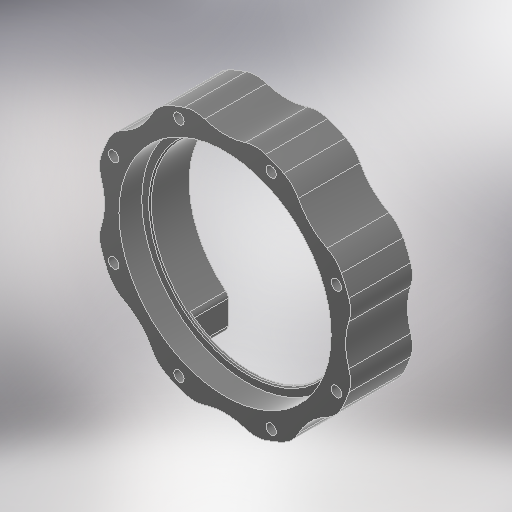
# Autodesk Inventor part: 3D_motor-spacer
Saved by Autodesk Inventor 2025.3 (Build 293356030, 356C)
## iProperties
Created: 2026-01-04
Part Number: 3D_motor-spacer
Material: 一般
Document SubType Name: Modeling
Designer: ibuki_ono
Density: 1 g/cm^3
Appearance: 滑らか - 黒
Author: ibuki_ono
## iProperties of the stored document 3D_motor-spacer_3D プリント.ipt
Created: 2026-02-11
Part Number: 3D_motor-spacer_3D プリント
Material: 一般
Document SubType Name: Modeling
Designer: ibuki_ono
Density: 1 g/cm^3
Appearance: 既定
Author: ibuki_ono
Autodesk Inventor part; units mm, degrees
ref_plane "YZ Plane" through (0, 0, 0) normal (1, 0, 0) x (0, 1, 0)
ref_plane "XZ Plane" through (0, 0, 0) normal (0, 1, 0) x (-1, 0, 0)
ref_plane "XY Plane" through (0, 0, 0) normal (0, 0, 1) x (1, 0, 0)
sketch "スケッチ1" plane through (0, 0, 0) normal (0, 0, 1) x (1, 0, 0)
  circle A0 centre (0, 0) radius 30
  circle A1 centre (0, 0) radius 40
  dimension "d0" = 60
  dimension "d1" = 80
  constraints: 2 centre point, 2 coincident
  measures "d0" diameter of A0
  measures "d1" diameter of A1
extrude "押し出し1" add sketch "スケッチ1" along normal mid plane 11
sketch "スケッチ2" plane through (0, 0, 5.5) normal (0, 0, 1) x (1, 0, 0)
  line L0 (0, 0) -> (34.1835, 14.1593) construction
  line L1 (0, 0) -> (30, 0) construction
  circle A0 centre (0, 0) radius 30 construction
  point P0 (34.1835, 14.1593)
  dimension "d21" = 37
  dimension "d23" = 22.5
  constraints: 4 end point, 1 coincident, 1 horizontal, 1 horizontal alignment, 1 other
  measures "d21" distance of L0.start L0.end
  measures "d23" angle of L0 L1
hole "穴1" at (34.1835, 14.1593, 5.5) direction (0, 0, -1) diameter 3.2 end through all
pattern_circular "円形状パターン1" count 8 over 360 about axis through (0, 0, 0) along (0, 0, 1) of "穴1"
sketch "スケッチ3" plane through (0, 0, 5.5) normal (0, 0, 1) x (1, 0, 0)
  circle A0 centre (34.1835, -14.1593) radius 1.6 projected
  circle A1 centre (14.1593, -34.1835) radius 1.6 projected
  circle A2 centre (-14.1593, -34.1835) radius 1.6 projected
  circle A3 centre (-34.1835, -14.1593) radius 1.6 projected
  circle A4 centre (-34.1835, 14.1593) radius 1.6 projected
  circle A5 centre (-14.1593, 34.1835) radius 1.6 projected
  circle A6 centre (14.1593, 34.1835) radius 1.6 projected
  circle A7 centre (34.1835, 14.1593) radius 1.6 projected
  circle A8 centre (0, 0) radius 40 projected
  circle A9 centre (0, 0) radius 30 projected
extrude "押し出し2" add sketch "スケッチ3" along normal blind 8 contours A8 | A9
sketch "スケッチ4" plane through (0, 0, 13.5) normal (0, 0, 1) x (1, 0, 0)
  circle A0 centre (0, 0) radius 32.55
  dimension "d18" = 65.1
  constraints: 1 centre point, 1 coincident
  measures "d18" diameter of A0
extrude "押し出し3" cut sketch "スケッチ4" against normal blind 7
sketch "スケッチ5" plane through (0, 0, 0) normal (0, 1, 0) x (-1, 0, 0)
  line L0 (30, -5.5) -> (-30, -5.5) projected
  line L1 (-30, 5.5) -> (30, 5.5) projected
  line L2 (-15.7593, 13.5) -> (-12.5593, 13.5) projected
  line L3 (-12.5593, -5.5) -> (-15.7593, -5.5) projected
  line L4 (12.5593, 13.5) -> (15.7593, 13.5) projected
  line L5 (15.7593, -5.5) -> (12.5593, -5.5) projected
  line L6 (-18, 5.5) -> (-18, -5.5)
  line L7 (18, 5.5) -> (18, -5.5)
  point P0 (0, 0)
  dimension "d42" = 36
  dimension "d43" = 18
  constraints: 4 end point, 4 point on line, 2 perpendicular
  measures "d42" distance between parallel lines of L7 L6
  measures "d43" distance from line of L7 point (0, 0)
extrude "押し出し4" cut sketch "スケッチ5" against normal through all
sketch "スケッチ6" plane through (0, 0, 5.5) normal (0, 0, -1) x (-1, 0, 0)
  arc A0 (18, -24) -> (-18, -24) centre (0, 0) ccw projected
  circle A1 centre (0, 0) radius 30
  point P0 (18, -24)
  constraints: 1 coincident, 3 other
extrude "押し出し5" cut sketch "スケッチ6" against normal through all
chamfer "面取り1" distance 0.4 angle 45 2 edges at (0, -30, 6.5) (0, 30, 6.5)
fillet "フィレット1" radius 2 8 edges at (-18, -35.7211, 2.75) (-18, -35.7211, -2.75) (-18, -24, 2.75) (-18, -24, -2.75) (18, -35.7211, -2.75) (18, -35.7211, 2.75) (18, -24, 2.75) (18, -24, -2.75)
sketch "スケッチ7" plane through (0, 0, 13.5) normal (0, 0, 1) x (1, 0, 0)
  circle A0 centre (0, 0) radius 40 projected
  arc A1 (-8.7719, 39.0263) -> (8.7719, 39.0263) centre (0, 57) ccw
  dimension "d34" = 20
  dimension "d35" = 57
  constraints: 4 point on circle, 1 centre point, 1 horizontal alignment, 1 vertical alignment
  measures "d34" radius of A1
  measures "d35" distance of point (0, 0) A1.centre
extrude "押し出し6" cut sketch "スケッチ7" against normal through all contours A1 A0 picked at (0, 38.9276)
fillet "フィレット2" radius 10 6 edges at (-8.7719, 39.0263, 9.5) (-8.7719, 39.0263, -2.75) (-8.7719, 39.0263, 2.75) (8.7719, 39.0263, 9.5) (8.7719, 39.0263, 2.75) (8.7719, 39.0263, -2.75)
pattern_circular "円形状パターン2" count 8 over 360 about axis through (0, 0, 0) along (0, 0, 1) of "押し出し6", "フィレット2"
equation "\"d43\" = 0.5 * d42"
